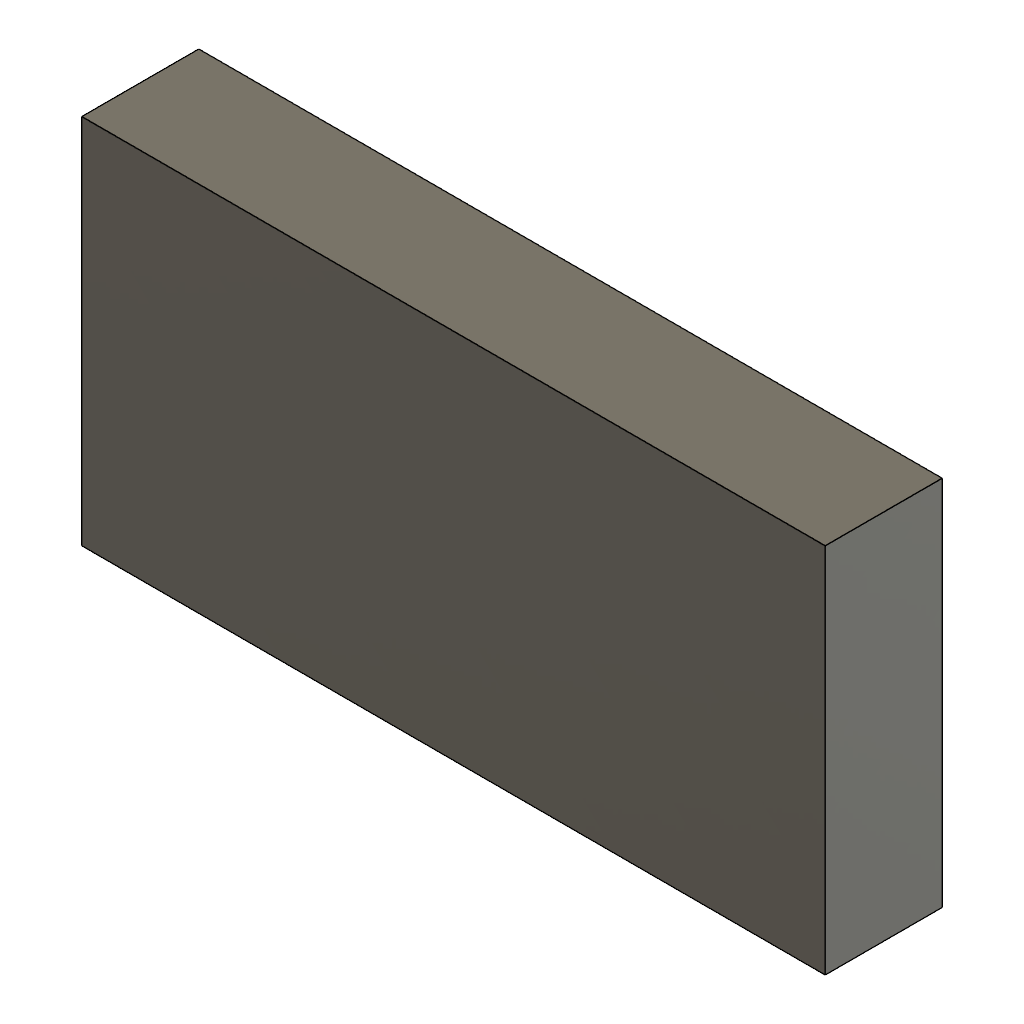
variation (Autodesk Fusion 360 design; units mm, degrees)
part number: 2026-11-23-13-15-49-007
Autodesk Fusion 360 part; units mm, degrees
sketch "Sketch1" plane through (0, 0, 0) normal (0, 0, 1) x (1, 0, 0)
  line L0 (0, 0) -> (40, 0)
  line L1 (40, 0) -> (40, 20)
  line L2 (40, 20) -> (0, 20)
  line L3 (0, 20) -> (0, 0)
extrude "ControlledBoss" add sketch "Sketch1" against normal blind 6.3
